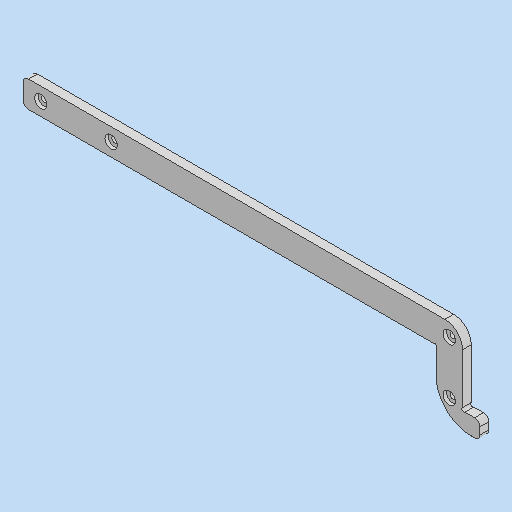
# Autodesk Inventor part: AP5.0_PC-stand4
Saved by Autodesk Inventor 2025.3 (Build 293356030, 356C)
## iProperties
Created: 2025-08-02
Part Number: AP5.0_PC-stand4
Material: 一般
Document SubType Name: Sheet Metal
Designer: ibuki_ono
Density: 1 g/cm^3
Sheet Metal Rule: Default
Appearance: 既定
Author: ibuki_ono
Autodesk Inventor part; units mm, degrees
ref_plane "YZ Plane" through (0, 0, 0) normal (1, 0, 0) x (0, 1, 0)
ref_plane "XZ Plane" through (0, 0, 0) normal (0, 1, 0) x (-1, 0, 0)
ref_plane "XY Plane" through (0, 0, 0) normal (0, 0, 1) x (1, 0, 0)
sketch "スケッチ1" plane through (0, 0, 0) normal (0, 0, 1) x (1, 0, 0)
  line L0 (-125, -7.5) -> (125, -7.5)
  line L1 (125, -7.5) -> (125, 7.5)
  line L2 (125, 7.5) -> (-125, 7.5)
  line L3 (-125, 7.5) -> (-125, -7.5)
  line L4 (-125, -7.5) -> (125, 7.5) construction
  line L5 (125, -7.5) -> (-125, 7.5) construction
  line L6 (125, 7.5) -> (110, 7.5)
  line L7 (110, 7.5) -> (110, -32.5)
  line L8 (110, -32.5) -> (125, -32.5)
  line L9 (125, -32.5) -> (125, 7.5)
  line L10 (110, -32.5) -> (135, -32.5)
  line L11 (135, -32.5) -> (135, -42.5)
  line L12 (135, -42.5) -> (110, -42.5)
  line L13 (110, -42.5) -> (110, -32.5)
  point P0 (0, 0)
  point P1 (110, -7.5)
  dimension "d0" = 250
  dimension "d1" = 15
  dimension "d2" = 15
  dimension "d3" = 40
  dimension "d4" = 25
  dimension "d5" = 10
  constraints: 28 end point, 6 parallel, 3 horizontal, 3 perpendicular, 2 midpoint
  measures "d0" distance of L2.end L1.end
  measures "d1" distance of L1.end L0.end
  measures "d2" distance of L8.end L7.end
  measures "d3" distance of L7.end L6.end
  measures "d4" distance of L11.end L12.end
  measures "d5" distance of L10.end L11.end
extrude "押し出し1" add sketch "スケッチ1" along normal blind 5
sketch "スケッチ2" plane through (0, 0, 5) normal (0, 0, 1) x (1, 0, 0)
  line L0 (-125, 7.5) -> (-125, -7.5) projected
  line L1 (-125, 0) -> (-75, 0) construction
  line L2 (-125, 0) -> (-75, 0) construction
  point P0 (0, 0)
  point P1 (-115, 0)
  dimension "d8" = 50
  dimension "d9" = 0
  dimension "d10" = 10
  constraints: 4 end point, 2 horizontal, 1 coincident, 1 collinear, 1 midpoint, 1 point on line
  measures "d8" distance of L1.start L1.end
  measures "d9" distance between parallel lines of L1 L2
  measures "d10" distance from line of L0 point (-115, 0)
hole "穴1" at (-75, 0, 5) at (-115, 0, 5) direction (0, 0, -1) diameter 3.1 end through all counterbore diameter 7 counterbore depth 2
fillet "フィレット1" radius 20 1 edges at (110, -42.5, 2.5)
sketch "スケッチ3" plane through (0, 0, 5) normal (0, 0, 1) x (1, 0, 0)
  arc A0 (110, -22.5) -> (130, -42.5) centre (130, -22.5) ccw projected
  line L0 (130, -42.5) -> (135, -42.5) projected
  line L1 (135, -42.5) -> (135, -32.5) projected
  line L2 (135, -32.5) -> (125, -32.5) projected
  line L3 (125, -32.5) -> (125, 7.5) projected
  line L4 (125, 7.5) -> (-125, 7.5) projected
  line L5 (-125, 7.5) -> (-125, -7.5) projected
  line L6 (-125, -7.5) -> (110, -7.5) projected
  line L7 (110, -7.5) -> (110, -22.5) projected
  line L8 (-125, -7.5) -> (110, -7.5) projected
  line L9 (110, -7.5) -> (109.2575, -8.2425) construction
  line L10 (110, -7.5) -> (111.05, -7.5) construction
  circle A1 centre (109.2575, -8.2425) radius 1.05
  line L11 (135, -32.5) -> (125, -32.5) projected
  line L12 (125, -32.5) -> (125, 7.5) projected
  line L13 (125, -32.5) -> (125.7425, -31.7575) construction
  line L14 (125, -32.5) -> (126.05, -32.5) construction
  circle A2 centre (125.7425, -31.7575) radius 1.05
  point P0 (0, 0)
  point P1 (126.4849, -32.5)
  point P2 (125, -31.0151)
  dimension "d19" = 1.05
  dimension "d20" = 135
  dimension "d37" = 1.05
  dimension "d38" = 45
  constraints: 8 end point, 2 coincident, 2 equal length, 2 horizontal, 6 other
  measures "d19" distance of L6.end L9.end
  measures "d20" angle of L9 L10
  measures "d37" distance of L2.end L13.end
  measures "d38" angle of L14 L13
extrude "押し出し2" cut sketch "スケッチ3" against normal through all contours A1 L6 L7 | L7 A1 | L6 A1 | A2 L2 | A2 L3
fillet "フィレット3" radius 3 4 edges at (135, -32.5, 2.5) (135, -42.5, 2.5) (-125, -7.5, 2.5) (-125, 7.5, 2.5)
fillet "フィレット4" radius 10 1 edges at (125, 7.5, 2.5)
sketch "スケッチ4" plane through (0, 0, 5) normal (0, 0, 1) x (1, 0, 0)
  line L0 (125, -32.5) -> (125, -2.5) projected
  line L1 (117.5, 0) -> (117.5, -30) construction
  line L2 (117.5, 0) -> (147.5, 0) construction
  line L3 (115, 7.5) -> (-122, 7.5) construction
  point P0 (0, 0)
  point P1 (125, -30.5)
  dimension "d26" = 30
  dimension "d27" = 90
  dimension "d28" = 7.5
  dimension "d29" = 7.5
  constraints: 4 end point, 2 coincident, 1 horizontal, 1 perpendicular, 1 vertical
  measures "d26" distance of L1.start L1.end
  measures "d27" angle of L1 L2
  measures "d28" distance from line of L3 L1.start
  measures "d29" distance between parallel lines of L0 L1
hole "穴2" at (117.5, 0, 5) at (117.5, -30, 5) direction (0, 0, -1) diameter 3.1 end through all counterbore diameter 7 counterbore depth 2
equation "\"d16\" = Thickness"
equation "\"d29\" = d28"
equation "\"d35\" = Thickness"
equation "\"BendRadius\" = Thickness"
equation "\"BendReliefWidth\" = Thickness"
equation "\"BendReliefDepth\" = 0.5 * Thickness"
equation "\"TransitionRadius\" = BendRadius"
equation "\"JacobiRadiusSize\" = BendRadius"
equation "\"GapSize\" = Thickness"
equation "\"Thickness\" = 5"
